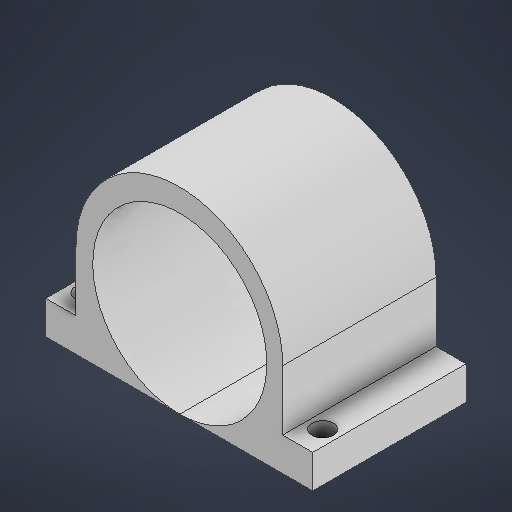
# Autodesk Inventor part: Roller Rod Mount
Saved by Autodesk Inventor 2026.3 (Build 303398000, 398)
## iProperties
Created: 2026-08-20
Part Number: Roller Rod Mount
Material: Generic
Document SubType Name: Modeling
Designer: User
Density: 1 g/cm^3
Appearance: Default
Author: User
Autodesk Inventor part; units mm, degrees
ref_plane "YZ Plane" through (0, 0, 0) normal (1, 0, 0) x (0, 1, 0)
ref_plane "XZ Plane" through (0, 0, 0) normal (0, 1, 0) x (-1, 0, 0)
ref_plane "XY Plane" through (0, 0, 0) normal (0, 0, 1) x (1, 0, 0)
sketch "Sketch4" plane through (0, 0, 0) normal (0, 0, 1) x (1, 0, 0)
  line L0 (0, 0) -> (40, 0)
  line L1 (40, 0) -> (40, 5)
  line L2 (0, 5) -> (0, 0)
  line L3 (0, 5) -> (4.5, 5)
  line L4 (40, 5) -> (35.5, 5)
  line L5 (4.5, 5) -> (4.5, 14)
  line L6 (35.5, 5) -> (35.5, 14)
  arc A0 (35.5, 14) -> (4.5, 14) centre (20, 14) ccw
  line L7 (40, 5) -> (35.5, 5)
  line L8 (4.5, 5) -> (0, 5)
  point P0 (20, 13)
  dimension "d13" = 40
  dimension "d14" = 5
  dimension "d18" = 4.5
  dimension "d19" = 4.5
  dimension "d20" = 9
  constraints: 18 end point, 3 parallel, 2 point on circle, 2 tangent, 2 vertical, 1 centre point, 1 horizontal, 1 perpendicular
  measures "d13" distance of L2.start L1.end
  measures "d14" distance of L0.end L1.end
  measures "d18" distance of L3.end L2.start
  measures "d19" distance of L4.end L1.end
  measures "d20" distance of L4.end L6.end
extrude "Extrusion3" add sketch "Sketch4" against normal blind 23
sketch "Sketch5" plane through (0, 0, 0) normal (0, 0, 1) x (1, 0, 0)
  line L0 (40, 0) -> (0, 0) projected
  circle A0 centre (20.0769, 13.05) radius 13.05
  dimension "d24" = 26.1
  constraints: 1 centre point
  measures "d24" diameter of A0
extrude "Extrusion4" cut sketch "Sketch5" against normal blind 21
sketch "Sketch6" plane through (35.5, 5, 0) normal (0, 1, 0) x (1, 0, 0)
  line L0 (4.5, 0) -> (4.5, 23) projected
  line L1 (-35.5, 0) -> (-35.5, 23) projected
  line L2 (-35.5, 11.5) -> (-33.25, 11.5)
  line L3 (2.25, 0) -> (2.25, 3.75)
  point P0 (-33.25, 3.75)
  constraints: 4 end point, 1 coincident, 1 horizontal, 1 midpoint
hole "Hole1" at (37.75, 5, -3.75) at (2.25, 5, -3.75) direction (0, -1, 0) diameter 3.2 end through all
body "Solid2"
